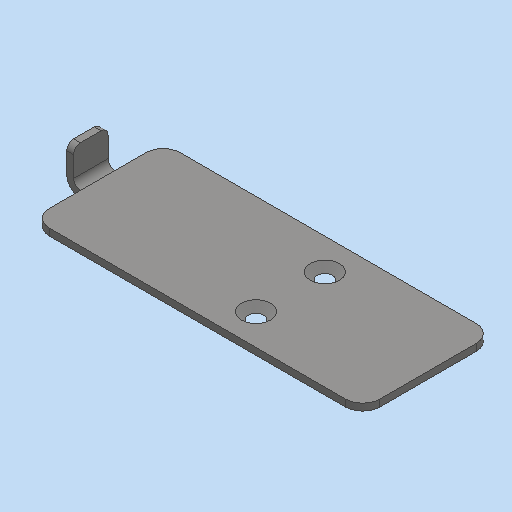
# Autodesk Inventor part: SE0004AN000_G01_109
Saved by Autodesk Inventor 2023.3 (Build 273359000, 359)
## iProperties
RuleStatus: InUse
Created: 2021-07-09
Part Number: SE0004AN000_G01_109
Material: 1.4301 X5CrNi18-10
Description: =<RBPARTNOTITLE2>
Document SubType Name: Blech
Designer: frt9bw
Mass: 57.8307 g
Surface Area: 80.4036 cm^2
Volume: 7.36697 cm^3
Density: 7.85 g/cm^3
Sheet Metal Rule: Standard_mm
Appearance: Stahl - rostfrei AnP
Vendor: ASW
AnP_Kategorie: 1
AnP_Material: =<Material>
MaxAbmaße: 12 x 38 x 100 (FM)
AnP_TemplVers: 20200821
RBDOCUMENTTYPE: DRF
RBDOCUMENTVERSION: 00
RBDRAWINGMAINSCALE: 1:1
RBDRAWINGMISSINGSPEC: --
RBDRAWINGVOLUME: --
RBDSV1: 0850
RBGBEDGESIN1: +0,5
RBGBEDGESIN2: +0,2
RBGBEDGESOUT1: -0,3
RBGBEDGESOUT2: -0,1
RBMATERIAL: =<Material>
RBMATMEETS: --
RBMATNO: =<Part Number>
RBPARTMADEOF: 12 x 38 x 100 (FM)
RBPARTNO: SIEHE MNR
RBPARTNOTITLE1: manufactured part
RBPARTNOTITLE2: Anfertigungsteil
RBPARTSAFETYINDICATOR: --
RBSURFACE: --
RBSURFACE2: --
RBZEDGESNORM: ISO13715:2002-06
RBZGENDIMCLASS: m
RBZGENDIMNORM: ISO 2768-1:1989-11
RBZGENGEOCLASS: H
RBZGENGEONORM: ISO 2768-2:1989-11
RBZSURFACENORM: ISO13D2:2002-02
RBZTOLERANCENORM: ISO 14405-1:2010-12
Author: frt9bw
Keywords: =<RBPARTMADEOF>
Comments: =<RBSURFACE2>
Revision Number: 01
Autodesk Inventor part; units mm, degrees
ref_plane "YZ Plane" through (0, 0, 0) normal (1, 0, 0) x (0, 1, 0)
ref_plane "XZ Plane" through (0, 0, 0) normal (0, 1, 0) x (-1, 0, 0)
ref_plane "XY Plane" through (0, 0, 0) normal (0, 0, 1) x (1, 0, 0)
sketch "Skizze1" plane through (0, 0, 0) normal (0, 0, 1) x (1, 0, 0)
  line L0 (0, 0) -> (100, 0)
  line L1 (100, 0) -> (100, 38)
  line L2 (100, 38) -> (0, 38)
  line L3 (0, 38) -> (0, 0)
  dimension "d0" = 100
  dimension "d1" = 38
  measures "d0" distance of L2.end L1.end
  measures "d1" distance of L1.end L0.end
extrude "Grobblech1" add sketch "Skizze1" along normal blind 2
sketch "Skizze2" plane through (2, 0, 0) normal (-1, 0, 0) x (0, -1, 0)
  line L0 (-38, 0) -> (0, 0)
  line L1 (0, 0) -> (0, 12)
  line L2 (0, 12) -> (-38, 12)
  line L3 (-38, 12) -> (-38, 0)
  constraints: 6 end point, 1 horizontal, 1 perpendicular, 1 vertical
edge flange "Lasche1" height 12 angle 90 thickness 2 bend radius 2 thickness toward (-1, 0, 0) relief tear relief width 2 relief depth 1 edges at (0, 19, 2) wall of the first edge with corners at (2, 38, 0) (2, 0, 0) (2, 0, 12) (2, 38, 12)
bend "Biegung1"
corner "Ecke1"
sketch "Skizze3" plane through (0, 0, 12) normal (0, -1, 0) x (1, 0, 0)
  line L0 (0, -8) -> (2, -8) projected
  line L1 (2, -8) -> (2, 0) projected
  line L2 (2, 0) -> (0, 0) projected
  line L3 (0, 0) -> (0, -8) projected
  line L4 (0, -8) -> (2, -8) projected
  arc A0 (0, -8) -> (4, -12) centre (4, -8) ccw projected
  line L5 (4, -10) -> (4, -12) projected
  arc A1 (2, -8) -> (4, -10) centre (4, -8) ccw projected
  point P0 (0, -12)
extrude "Extrusion1" cut sketch "Skizze3" against normal blind 14
sketch "Skizze4" plane through (0, 38, 12) normal (0, 1, 0) x (1, 0, 0)
  line L0 (2, 8) -> (0, 8) projected
  arc A0 (4, 10) -> (2, 8) centre (4, 8) ccw projected
  line L1 (4, 12) -> (4, 10) projected
  arc A1 (4, 12) -> (0, 8) centre (4, 8) ccw projected
  line L2 (2, 8) -> (0, 8) projected
  line L3 (0, 8) -> (0, 0) projected
  line L4 (2, 0) -> (0, 0) projected
  line L5 (2, 8) -> (2, 0) projected
  point P0 (0, 12)
  point P1 (0, 8)
extrude "Extrusion2" cut sketch "Skizze4" against normal blind 14
fillet "Rundung1" radius 5 3 edges at (4, 38, 1) (100, 0, 1) (100, 38, 1)
fillet "Rundung2" radius 2 2 edges at (1, 14, 12) (1, 24, 12)
sketch "Skizze5" plane through (0, 0, 2) normal (0, 0, 1) x (1, 0, 0)
  line L0 (9, 38) -> (95, 38) projected
  line L1 (100, 33) -> (100, 5) projected
  point P0 (0, 0)
  point P1 (60, 29)
  point P2 (60, 9)
  dimension "d19" = 20
  dimension "d20" = 9
  dimension "d21" = 40
  constraints: 1 vertical alignment
  measures "d19" distance of point (60, 9) point (60, 29)
  measures "d20" distance from line of L0 point (60, 29)
  measures "d21" distance from line of L1 point (60, 29)
hole "Bohrung1" at (60, 29, 2) at (60, 9, 2) direction (0, 0, -1) diameter 4.5 end through all countersink diameter 8.5 countersink angle 90
fillet "Rundung3" radius 5 1 edges at (4, 0, 1)
equation "\"d27\" = Stärke"
equation "\"d2\" = Stärke"
equation "\"d3\" = BreiteBiegungsfreistellung"
equation "\"d4\" = TiefeBiegungsfreistellung"
equation "\"d5\" = MinimalRest"
equation "\"d6\" = Übergangsradius"
equation "\"d9\" = Biegeradius"
equation "\"d10\" = GrößeEckenfreistellung"
equation "\"d11\" = Abstandsgröße"
equation "\"d12\" = JacobiRadiusGröße"
equation "\"Biegeradius\" = Stärke"
equation "\"BreiteBiegungsfreistellung\" = Stärke"
equation "\"TiefeBiegungsfreistellung\" = 0.5 * Stärke"
equation "\"GrößeEckenfreistellung\" = 4 * Stärke"
equation "\"MinimalRest\" = 2 * Stärke"
equation "\"Übergangsradius\" = Biegeradius"
equation "\"JacobiRadiusGröße\" = Biegeradius"
equation "\"Abstandsgröße\" = Stärke"
equation "\"Stärke\" = 2"
